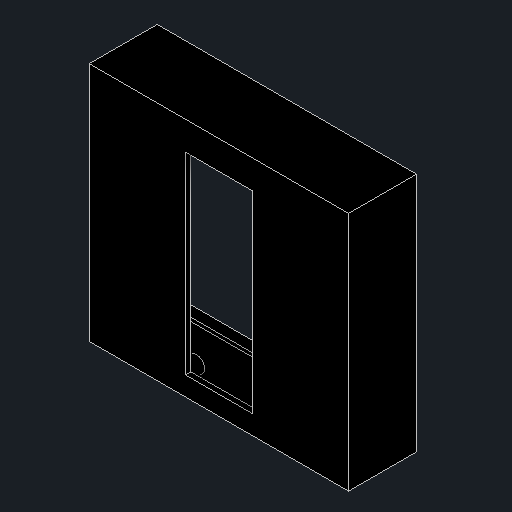
# Autodesk Inventor part: Enclosure Lid
Saved by Autodesk Inventor 2027.2 (Build 312334000, 334)
## iProperties
Created: 2026-11-11
Part Number: Enclosure Lid
Material: Generic
Description: Enclosure lid: LCD window (LCD rotated 90 deg) and bosses, board clamps, locating lip
Document SubType Name: Modeling
Designer: isaac
Density: 1 g/cm^3
Appearance: Black
Author: isaac
Autodesk Inventor part; units mm, degrees
ref_plane "Work Plane1" through (0, 0, 4) normal (0, 0, 1) x (1, 0, 0)
sketch "Sketch1" plane through (0, 0, 4) normal (0, 0, 1) x (1, 0, 0)
  line L0 (-3.5, -8) -> (93, -8)
  line L1 (93, -8) -> (93, 81.5)
  line L2 (93, 81.5) -> (-3.5, 81.5)
  line L3 (-3.5, 81.5) -> (-3.5, -8)
  constraints: 8 end point, 2 parallel, 1 horizontal, 1 perpendicular
extrude "Shell" add sketch "Sketch1" along normal blind 25.3
ref_plane "Work Plane2" through (0, 0, 4) normal (0, 0, 1) x (1, 0, 0)
sketch "Sketch2" plane through (0, 0, 4) normal (0, 0, 1) x (1, 0, 0)
  line L0 (-1.5, -6) -> (91, -6)
  line L1 (91, -6) -> (91, 79.5)
  line L2 (91, 79.5) -> (-1.5, 79.5)
  line L3 (-1.5, 79.5) -> (-1.5, -6)
  constraints: 8 end point, 2 parallel, 1 horizontal, 1 perpendicular
extrude "Pocket" cut sketch "Sketch2" along normal blind 23.3
ref_plane "Work Plane3" through (0, 0, 2) normal (0, 0, 1) x (1, 0, 0)
sketch "Sketch3" plane through (0, 0, 2) normal (0, 0, 1) x (1, 0, 0)
  line L0 (-1.3, -5.8) -> (90.8, -5.8)
  line L1 (90.8, -5.8) -> (90.8, 79.3)
  line L2 (90.8, 79.3) -> (-1.3, 79.3)
  line L3 (-1.3, 79.3) -> (-1.3, -5.8)
  constraints: 8 end point, 2 parallel, 1 horizontal, 1 perpendicular
extrude "Lip" add sketch "Sketch3" along normal blind 4
ref_plane "Work Plane4" through (0, 0, 4) normal (0, 0, 1) x (1, 0, 0)
sketch "Sketch4" plane through (0, 0, 4) normal (0, 0, 1) x (1, 0, 0)
  line L0 (-1.5, -6) -> (91, -6)
  line L1 (91, -6) -> (91, 79.5)
  line L2 (91, 79.5) -> (-1.5, 79.5)
  line L3 (-1.5, 79.5) -> (-1.5, -6)
  constraints: 8 end point, 2 parallel, 1 horizontal, 1 perpendicular
extrude "Lip bridge" add sketch "Sketch4" along normal blind 2
ref_plane "Work Plane5" through (0, 0, 2) normal (0, 0, 1) x (1, 0, 0)
sketch "Sketch5" plane through (0, 0, 2) normal (0, 0, 1) x (1, 0, 0)
  line L0 (-0.1, -4.6) -> (89.6, -4.6)
  line L1 (89.6, -4.6) -> (89.6, 78.1)
  line L2 (89.6, 78.1) -> (-0.1, 78.1)
  line L3 (-0.1, 78.1) -> (-0.1, -4.6)
  constraints: 8 end point, 2 parallel, 1 horizontal, 1 perpendicular
extrude "Lip inside" cut sketch "Sketch5" along normal blind 8
ref_plane "Work Plane6" through (0, 0, 27.3) normal (0, 0, 1) x (1, 0, 0)
sketch "Sketch6" plane through (0, 0, 27.3) normal (0, 0, 1) x (1, 0, 0)
  line L0 (32.35, -0.9) -> (57.15, -0.9)
  line L1 (57.15, -0.9) -> (57.15, 70.9)
  line L2 (57.15, 70.9) -> (32.35, 70.9)
  line L3 (32.35, 70.9) -> (32.35, -0.9)
  constraints: 8 end point, 2 parallel, 1 horizontal, 1 perpendicular
extrude "LCD window" cut sketch "Sketch6" along normal blind 2
ref_plane "Work Plane7" through (0, 0, 22.1) normal (0, 0, 1) x (1, 0, 0)
sketch "Sketch7" plane through (0, 0, 22.1) normal (0, 0, 1) x (1, 0, 0)
  circle A0 centre (29.25, 72.5) radius 3
  circle A1 centre (29.25, -2.5) radius 3
  circle A2 centre (60.25, 72.5) radius 3
  circle A3 centre (60.25, -2.5) radius 3
  constraints: 4 centre point
extrude "LCD bosses" add sketch "Sketch7" along normal blind 5.2
ref_plane "Work Plane8" through (0, 0, 22.1) normal (0, 0, 1) x (1, 0, 0)
sketch "Sketch8" plane through (0, 0, 22.1) normal (0, 0, 1) x (1, 0, 0)
  circle A0 centre (29.25, 72.5) radius 1.25
  circle A1 centre (29.25, -2.5) radius 1.25
  circle A2 centre (60.25, 72.5) radius 1.25
  circle A3 centre (60.25, -2.5) radius 1.25
  constraints: 4 centre point
extrude "LCD screw holes" cut sketch "Sketch8" along normal blind 4
ref_plane "Work Plane9" through (0, 0, 1.7) normal (0, 0, 1) x (1, 0, 0)
sketch "Sketch9" plane through (0, 0, 1.7) normal (0, 0, 1) x (1, 0, 0)
  line L0 (0, 0) -> (3.5, 0)
  line L1 (3.5, 0) -> (3.5, 3.5)
  line L2 (3.5, 3.5) -> (0, 3.5)
  line L3 (0, 3.5) -> (0, 0)
  line L4 (86.5, 0) -> (90, 0)
  line L5 (90, 0) -> (90, 3.5)
  line L6 (90, 3.5) -> (86.5, 3.5)
  line L7 (86.5, 3.5) -> (86.5, 0)
  line L8 (0, 66.5) -> (3.5, 66.5)
  line L9 (3.5, 66.5) -> (3.5, 70)
  line L10 (3.5, 70) -> (0, 70)
  line L11 (0, 70) -> (0, 66.5)
  line L12 (86.5, 66.5) -> (90, 66.5)
  line L13 (90, 66.5) -> (90, 70)
  line L14 (90, 70) -> (86.5, 70)
  line L15 (86.5, 70) -> (86.5, 66.5)
  constraints: 32 end point, 8 parallel, 4 horizontal, 4 perpendicular
extrude "Board clamps" add sketch "Sketch9" along normal blind 25.6
body "Solid1"
